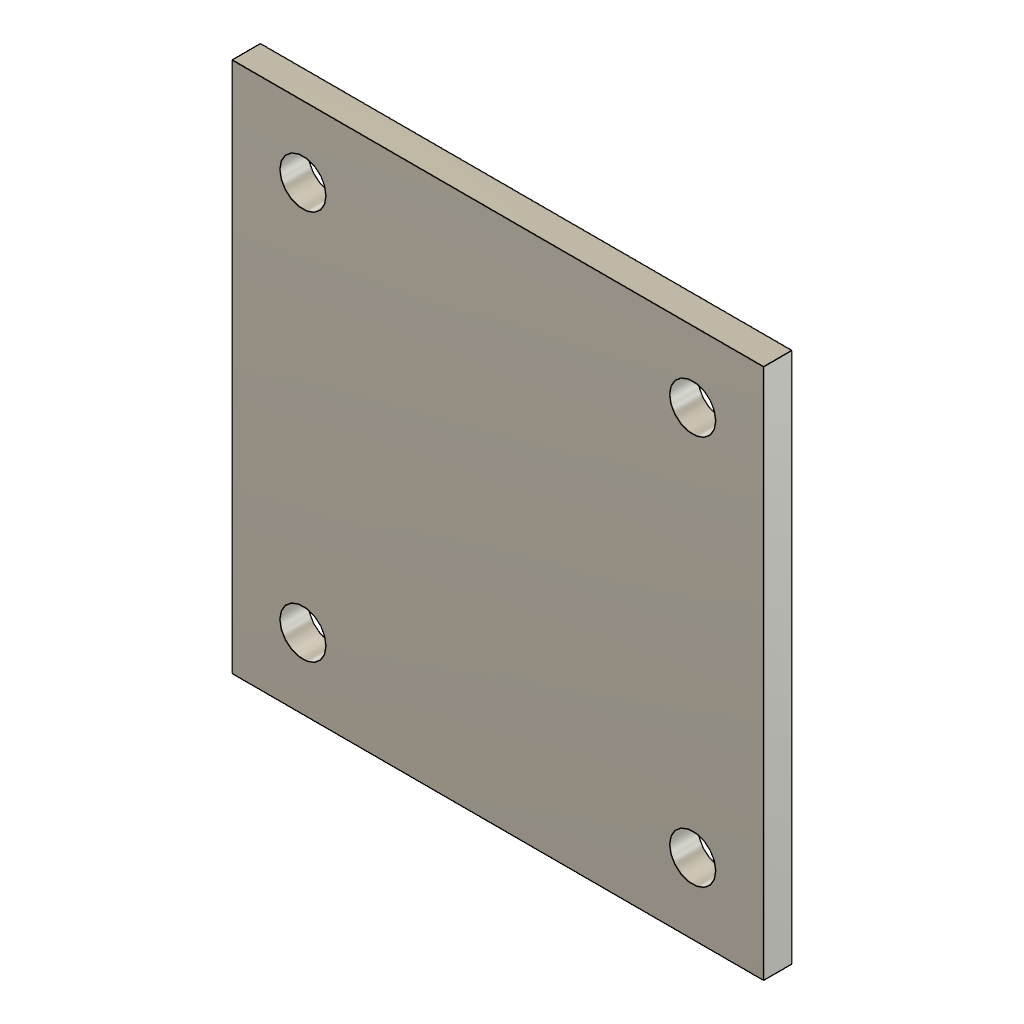
DRR_M1_bolt_down_plate (Autodesk Fusion 360 design; units mm, degrees)
part number: 2026-11-05-14-50-53-691
Autodesk Fusion 360 part; units mm, degrees
sketch "Sketch1" plane through (0, 0, 0) normal (0, 0, 1) x (1, 0, 0)
  line L0 (225, 279) -> (375, 279)
  line L1 (375, 279) -> (375, 429)
  line L2 (375, 429) -> (225, 429)
  line L3 (225, 429) -> (225, 279)
  circle A0 centre (245, 299) radius 6.5
  circle A1 centre (245, 409) radius 6.5
  circle A2 centre (355, 299) radius 6.5
  circle A3 centre (355, 409) radius 6.5
  dimension "d2121" = 225
  dimension "d2122" = 279
  dimension "d2123" = 375
  dimension "d2124" = 429
  dimension "d2125" = 245
  dimension "d2126" = 299
  dimension "d2127" = 13
  dimension "d2128" = 409
  dimension "d2129" = 13
  dimension "d2130" = 355
  dimension "d2131" = 13
  dimension "d2132" = 13
  constraint horizontal L0.start L0.end
  constraint vertical L0.end L1.end
  constraint vertical L0.start L2.end
  constraint horizontal L1.end L2.end
  constraint vertical A0.centre A1.centre
  constraint horizontal A0.centre A2.centre
  constraint vertical A2.centre A3.centre
  constraint horizontal A1.centre A3.centre
  measures "d2121" horizontal distance of origin L0.start
  measures "d2122" vertical distance of origin L0.start
  measures "d2123" horizontal distance of origin L0.end
  measures "d2124" vertical distance of origin L1.end
  measures "d2125" horizontal distance of origin A0.centre
  measures "d2126" vertical distance of origin A0.centre
  measures "d2127" diameter of A0
  measures "d2128" vertical distance of origin A1.centre
  measures "d2129" diameter of A1
  measures "d2130" horizontal distance of origin A2.centre
  measures "d2131" diameter of A2
  measures "d2132" diameter of A3
extrude "Extrude1" add sketch "Sketch1" along normal blind 8
equation "d2121 = ( ( frame_inset ) - foot_plate_w / 2 )"
equation "d2122 = ( ( ( rail_cc / 2 ) ) - foot_plate_w / 2 )"
equation "d2123 = ( ( frame_inset ) + foot_plate_w / 2 )"
equation "d2124 = ( ( ( rail_cc / 2 ) ) + foot_plate_w / 2 )"
equation "d2125 = ( ( frame_inset ) - foot_bolt_pitch / 2 )"
equation "d2126 = ( ( ( rail_cc / 2 ) ) - foot_bolt_pitch / 2 )"
equation "d2127 = foot_bolt_d"
equation "d2128 = ( ( ( rail_cc / 2 ) ) + foot_bolt_pitch / 2 )"
equation "d2129 = foot_bolt_d"
equation "d2130 = ( ( frame_inset ) + foot_bolt_pitch / 2 )"
equation "d2131 = foot_bolt_d"
equation "d2132 = foot_bolt_d"
equation "d2133 = ( foot_plate_t ) - ( 0 mm )"
equation "body_width = 508 mm" comment "spec: body width, design value"
equation "side_clear = 25 mm" comment "spec: gap between body and cap each side"
equation "rail_gap = body_width + 2 * side_clear" comment "spec: inner gap between caps"
equation "cap_width = 150 mm" comment "spec"
equation "frame_inset = 300 mm" comment "spec: U-frame position from section end"
equation "rail_cc = rail_gap + cap_width" comment "derived: rail centre-to-centre"
equation "foot_plate_w = 150 mm" comment "assumed: bolt-down plate"
equation "foot_plate_t = 8 mm" comment "assumed"
equation "foot_bolt_d = 13 mm" comment "assumed"
equation "foot_bolt_pitch = 110 mm" comment "assumed"
named bodies: "Plate R1"
